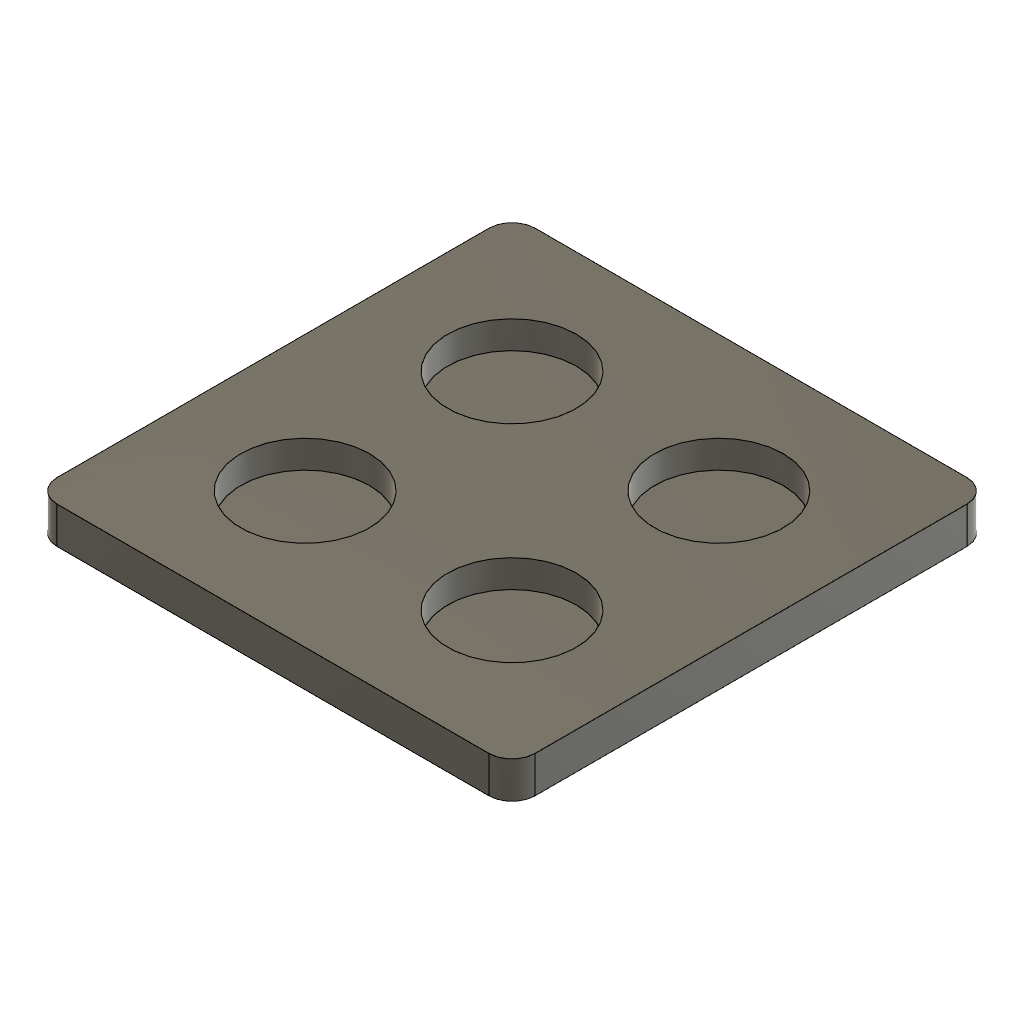
cay_tepsisi (Autodesk Fusion 360 design; units mm, degrees)
part number: 2026-10-11-11-31-50-236
Autodesk Fusion 360 part; units mm, degrees
sketch "Sketch1" plane through (0, 0, 0) normal (0, 1, 0) x (1, 0, 0)
  line L0 (104, 104) -> (-104, 104)
  line L1 (-104, 104) -> (-104, -104)
  line L2 (-104, -104) -> (104, -104)
  line L3 (104, -104) -> (104, 104)
  dimension "d7" = 208
  dimension "d8" = 208
  measures "d7" horizontal distance of L0.start L0.end
  measures "d8" vertical distance of L0.end L1.end
extrude "Extrude1" add sketch "Sketch1" along normal blind 16
sketch "Sketch2" plane through (0, 16, 0) normal (0, 1, 0) x (0, 0, 1)
  line L0 (104, 104) -> (-104, 104)
  line L1 (-104, 104) -> (-104, -104)
  line L2 (-104, -104) -> (104, -104)
  line L3 (104, -104) -> (104, 104)
  circle A0 centre (-45, -45) radius 28
  circle A1 centre (45, -45) radius 28
  circle A2 centre (-45, 45) radius 28
  circle A3 centre (45, 45) radius 28
  dimension "d11" = 56
  dimension "d12" = 56
  dimension "d13" = 56
  dimension "d14" = 56
  measures "d11" diameter of A0
  measures "d12" diameter of A1
  measures "d13" diameter of A2
  measures "d14" diameter of A3
extrude "Extrude2" cut sketch "Sketch2" against normal blind 12 contours A0 | A1 | A2 | A3
fillet "Fillet1" radius 10 4 edges at (104, 8, 104) (-104, 8, 104) (-104, 8, -104) (104, 8, -104)
shell "Shell1" thickness 2.4 removed faces 1 at (-34.6667, 0, 38)
equation "bardak_cap = 56 mm"
equation "yuva_derinlik = 12 mm"
equation "aralik = 90 mm"
equation "kalinlik = 16 mm"
equation "kenar = 14 mm"
equation "kose = 10 mm"
equation "d7 = 2 * aralik + 2 * kenar"
equation "d8 = 2 * aralik + 2 * kenar"
equation "d9 = kalinlik"
equation "d11 = bardak_cap"
equation "d12 = bardak_cap"
equation "d13 = bardak_cap"
equation "d14 = bardak_cap"
equation "d15 = -( yuva_derinlik )"
equation "d18 = kose"
equation "duvar = 2.4 mm" comment "kabuk duvarÄ± (0,4 mm nozul Ã 6)"
equation "d20 = duvar"
named bodies: "tepsi"
